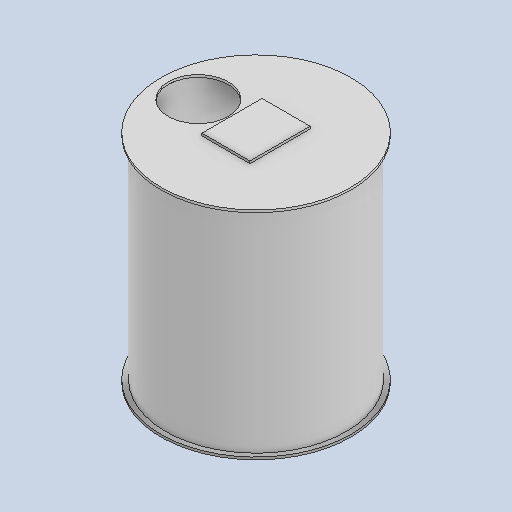
# Autodesk Inventor part: RDS-GHN300-2000 Tank2
Saved by Autodesk Inventor 2026 (Build 300175000, 175)
## iProperties
Created: 2026-10-27
Part Number: RDS-GHN300-2000 Tank2
Material: Типовые
Document SubType Name: Modeling
Designer: user
Density: 1 g/cm^3
Appearance: По умолчанию
Author: user
Autodesk Inventor part; units mm, degrees
ref_plane "YZ Plane" through (0, 0, 0) normal (1, 0, 0) x (0, 1, 0)
ref_plane "XZ Plane" through (0, 0, 0) normal (0, 1, 0) x (-1, 0, 0)
ref_plane "XY Plane" through (0, 0, 0) normal (0, 0, 1) x (1, 0, 0)
sketch "Эскиз1" plane through (0, 0, 0) normal (0, 1, 0) x (-1, 0, 0)
  circle A0 centre (0, 0) radius 375
  dimension "d0" = 750
  constraints: 1 centre point, 1 coincident
  measures "d0" diameter of A0
extrude "Выдавливание1" add sketch "Эскиз1" along normal blind 900
shell "Оболочка1" thickness 10 removed faces 0
sketch "Эскиз2" plane through (0, 0, 0) normal (0, -1, 0) x (1, 0, 0)
  circle A0 centre (0, 0) radius 375 projected
  circle A1 centre (0, 0) radius 365 projected
  circle A2 centre (0, 0) radius 395
  dimension "d4" = 790
  constraints: 1 centre point, 1 coincident
  measures "d4" diameter of A2
extrude "Выдавливание2" add sketch "Эскиз2" against normal blind 10 contours A0 | A1 | A2
sketch "Эскиз3" plane through (0, 900, 0) normal (0, 1, 0) x (1, 0, 0)
  circle A0 centre (0, 0) radius 395
  dimension "d7" = 790
  constraints: 1 centre point, 1 coincident
  measures "d7" diameter of A0
extrude "Выдавливание3" add sketch "Эскиз3" against normal blind 10
sketch "Эскиз4" plane through (0, 900, 0) normal (0, 1, 0) x (1, 0, 0)
  line L0 (-100, -125) -> (100, -125)
  line L1 (100, -125) -> (100, 125)
  line L2 (100, 125) -> (-100, 125)
  line L3 (-100, 125) -> (-100, -125)
  line L4 (-100, -125) -> (100, 125) construction
  line L5 (100, -125) -> (-100, 125) construction
  point P0 (0, 0)
  dimension "d10" = 200
  dimension "d11" = 250
  constraints: 12 end point, 2 midpoint, 2 parallel, 1 horizontal, 1 perpendicular
  measures "d10" distance of L2.end L1.end
  measures "d11" distance of L1.end L0.end
extrude "Выдавливание4" add sketch "Эскиз4" along normal blind 10
sketch "Эскиз5" plane through (0, 900, 0) normal (0, 1, 0) x (1, 0, 0)
  circle A0 centre (-240, 0) radius 125
  circle A1 centre (0, 0) radius 395 projected
  dimension "d14" = 250
  dimension "d15" = 240
  constraints: 1 centre point
  measures "d14" diameter of A0
  measures "d15" distance of A0.centre point (0, 0)
extrude "Выдавливание5" cut sketch "Эскиз5" against normal blind 10 contours A0
